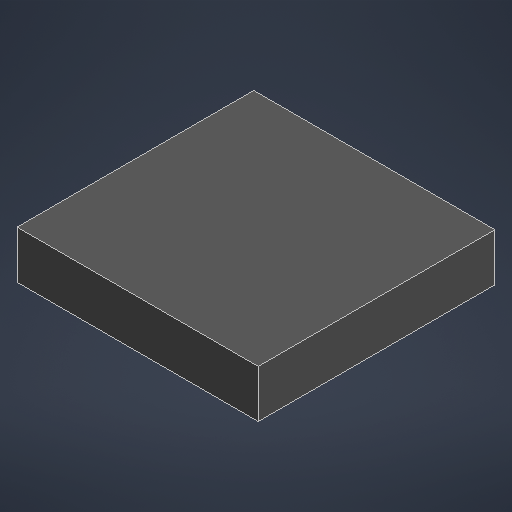
# Autodesk Inventor part: MiniPC
Saved by Autodesk Inventor 2026 (Build 300175050, 175E)
## iProperties
Created: 2026-07-16
Part Number: MiniPC
Material: MiniPC
Document SubType Name: Modeling
Designer: Anura
Density: 1.02416 g/cm^3
Appearance: Generic
Author: Anura
Autodesk Inventor part; units mm, degrees
ref_plane "YZ Plane" through (0, 0, 0) normal (1, 0, 0) x (0, 1, 0)
ref_plane "XZ Plane" through (0, 0, 0) normal (0, 1, 0) x (-1, 0, 0)
ref_plane "XY Plane" through (0, 0, 0) normal (0, 0, 1) x (1, 0, 0)
sketch "Sketch1" plane through (0, 0, 0) normal (0, 1, 0) x (-1, 0, 0)
  line L0 (0, 0) -> (182, 0)
  line L1 (182, 0) -> (182, -178.6)
  line L2 (182, -178.6) -> (0, -178.6)
  line L3 (0, -178.6) -> (0, 0)
  dimension "d0" = 182
  dimension "d1" = 178.6
  constraints: 8 end point, 2 parallel, 1 horizontal, 1 perpendicular
  measures "d0" distance of L1.end L2.end
  measures "d1" distance of L0.end L1.end
extrude "Extrusion1" add sketch "Sketch1" along normal blind 36
body "Solid1"
